Autodesk Fusion 360 part; units mm, degrees
(part 2 of 2)
sketch "Boceto2" plane through (0, 0, 0) normal (-1, 0, 0) x (0, 0, 1)
  circle A0 centre (0, 0) radius 6.5
  circle A1 centre (0, 0) radius 12.5
  line L0 (-12.5, 0) -> (12.5, 0)
  line L1 (12.5, 0) -> (12.5, 50)
  line L2 (12.5, 50) -> (-12.5, 50)
  line L3 (-12.5, 50) -> (-12.5, 0)
  dimension "d5" = 25
  dimension "d6" = 50
  constraint horizontal L0
  constraint vertical L1
  constraint horizontal L2
  constraint vertical L3
  constraint coincident A1 L0.start
  measures "d5" distance of L0.start L0.end
  measures "d6" distance of L0.start L2.end
extrude "Extruir2" add sketch "Boceto2" against normal blind 25 contours A1 L1 L2 L3
sketch "Boceto3" plane through (0, 50, 0) normal (0, 1, 0) x (-1, 0, 0)
  line L0 (0, -12.5) -> (0, 12.5)
  line L1 (0, 12.5) -> (-25, 12.5)
  line L2 (-25, 12.5) -> (-25, -12.5)
  line L3 (-25, -12.5) -> (0, -12.5)
  circle A0 centre (-12.5, 0) radius 5.2
  dimension "d9" = 10.4
  measures "d9" diameter of A0
extrude "Extruir3" cut sketch "Boceto3" against normal blind 35 contours A0
fillet "Empalme1" radius 6 3 edges at (0, 25, -12.5) (0, -12.5, 0) (0, 25, 12.5)
fillet "Empalme1" radius 6 2 edges at (25, 25, -12.5) (25, 25, 12.5)
fillet "Empalme2" radius 10 3 edges at (22.9076, 5.8382, -11.0516) (25, 12.5, 0) (22.9076, 5.8382, 11.0516)
ref_plane "PlanoDeObra1" through (59.5576, 0, 12.5) normal (0, 0, 1) x (0, 1, 0)
sketch "Boceto4" plane through (0, 0, 12.5) normal (0, 0, 1) x (1, 0, 0)
  circle A0 centre (60, 0) radius 1.925
  circle A1 centre (12.5, 0) radius 1.925
  circle A2 centre (12.5, 41.4419) radius 1.669
  dimension "d19" = 3.85
  dimension "d20" = 60
  dimension "d23" = 3.85
  dimension "d24" = 12.5
  measures "d19" diameter of A0
  measures "d20" distance of origin A0.centre
  measures "d23" diameter of A1
  measures "d24" distance of origin A1.centre
extrude "Extruir4" cut sketch "Boceto4" against normal blind 25
equation "d24 = ( 25 / 2 ) * 1 mm"

design "soporte_final_de_carrera"
Autodesk Fusion 360 part; units mm, degrees
sketch "Boceto1" plane through (0, 0, 0) normal (0, 1, 0) x (1, 0, 0)
sketch "Boceto2" plane through (0, 0, 0) normal (0, 1, 0) x (1, 0, 0)
  line L0 (-1.2963, -16.3865) -> (28.7033, -16.237)
  line L1 (-0.8694, -11.1998) -> (-1.2963, -16.3865)
  line L2 (5.0335, -0.4337) -> (4.1469, -11.2061)
  line L3 (28.7033, -11.237) -> (-0.8694, -11.1998)
  line L4 (28.7033, -16.237) -> (28.7033, -11.237)
  line L5 (-0.8694, -11.1998) -> (0.0504, -0.0236)
  line L6 (0, 0) -> (0.0922, -18.4956) construction
  line L7 (4.1469, -11.2061) -> (5.8748, 9.7875)
  line L8 (5.8748, 9.7875) -> (0.8916, 10.1976)
  line L9 (0.8916, 10.1976) -> (0.0504, -0.0236)
  point P0 (3.4743, -16.237)
  point P1 (-1.1967, -15.176)
  point P2 (-1.5762, -19.7876)
  dimension "d1" = 5
  dimension "d2" = 5
  dimension "d3" = 5.1866
  dimension "d4" = 4.991
  constraint coincident L2.end L3
  constraint coincident L6.start origin
  constraint perpendicular L0 L6
  constraint parallel L2 L7
  constraint perpendicular L5 L8
  measures "d1" distance of L3.start L0.end
  measures "d2" distance of L2.start L5.end
  measures "d3" vertical distance of L1.start L0.start
  measures "d4" angle of L1 L6
extrude "Extruir1" add sketch "Boceto2" along normal blind 20
sketch "Boceto3" plane through (5.0351, 0, 0.4144) normal (0.99663, 0, 0.082025) x (0.082025, 0, -0.99663)
  line L0 (-10.8282, 0) -> (10.2364, 0)
  line L1 (10.2364, 20) -> (-10.8282, 20)
  line L2 (-10.8282, 20) -> (-10.8282, 0)
  line L3 (10.2364, 0) -> (10.2364, 25.0205) construction
  line L4 (10.2364, 0) -> (-19.9849, 0) construction
  circle A0 centre (4.7914, 15.5) radius 1.95
  circle A1 centre (4.7914, 4.5) radius 1.95
  line L5 (10.2364, 0) -> (10.2364, 20)
  dimension "d7" = 3.9
  dimension "d8" = 5.445
  dimension "d9" = 4.5
  dimension "d10" = 3.9
  dimension "d11" = 4.5
  dimension "d12" = 5.445
  constraint coincident L0.end L3.start
  constraint perpendicular L0 L3
  measures "d7" diameter of A0
  measures "d8" distance of L3 A0.centre
  measures "d9" distance of L1 A0.centre
  measures "d10" diameter of A1
  measures "d11" distance of L4 A1.centre
  measures "d12" distance of L3 A1.centre
extrude "Extruir2" cut sketch "Boceto3" against normal blind 5 contours A0 | A1
fillet "Empalme1" radius 1.2 2 edges at (5.279, 5.2052, -2.5489) (5.279, 16.2052, -2.5489)
sketch "Boceto4" plane through (0.0816, 0, 16.3796) normal (0.004984, 0, 0.999988) x (0.999988, 0, -0.004984)
  line L0 (-1.378, 0) -> (28.622, 0)
  line L1 (28.622, 0) -> (28.622, 20)
  line L2 (28.622, 20) -> (-1.378, 20)
  line L3 (-1.378, 20) -> (-1.378, 0)
  line L4 (-0.378, 2.01) -> (27.622, 2.01)
  line L5 (27.622, 2.01) -> (27.622, 18.01)
  line L6 (27.622, 18.01) -> (-0.378, 18.01)
  line L7 (-0.378, 18.01) -> (-0.378, 2.01)
  line L8 (-0.378, 2.01) -> (27.622, 18.01) construction
  line L9 (27.622, 2.01) -> (-0.378, 18.01) construction
  circle A0 centre (2.292, 15.34) radius 1.55
  line L10 (13.622, 8.2976) -> (13.622, 12.2565) construction
  line L11 (11.7827, 10.01) -> (15.7906, 10.01) construction
  circle A1 centre (24.952, 15.34) radius 1.55
  circle A2 centre (24.952, 4.68) radius 1.55
  circle A3 centre (2.292, 4.68) radius 1.55
  point P0 (13.622, 10.01)
  dimension "d17" = 28
  dimension "d18" = 16
  dimension "d19" = 3.1
  dimension "d20" = 2.67
  dimension "d21" = 2.67
  constraint horizontal L4
  constraint perpendicular L4 L5
  constraint parallel L4 L6
  constraint parallel L5 L7
  constraint coincident L8 P0
  constraint coincident L9 P0
  constraint perpendicular L2 L10
  constraint perpendicular L10 L11
  constraint symmetric A0 L10 A1
  constraint symmetric A0 L11 A3
  constraint symmetric L11 A1 A2
  measures "d17" distance of L5.end L6.end
  measures "d18" distance of L4.end L5.end
  measures "d19" diameter of A0
  measures "d20" distance of L6 A0.centre
  measures "d21" distance of L7 A0.centre
extrude "Extruir3" cut sketch "Boceto4" against normal blind 6 contours A0 | A1 | A2 | A3
fillet "Empalme2" radius 9 1 edges at (4.1469, 10, 11.2061)
equation "d8 = ( 10.89 / 2 ) * 1 mm"
equation "d20 = 1.12 mm + ( 3.1 / 2 ) * 1 mm"
equation "d21 = 1.12 mm + ( 3.1 / 2 ) * 1 mm"
